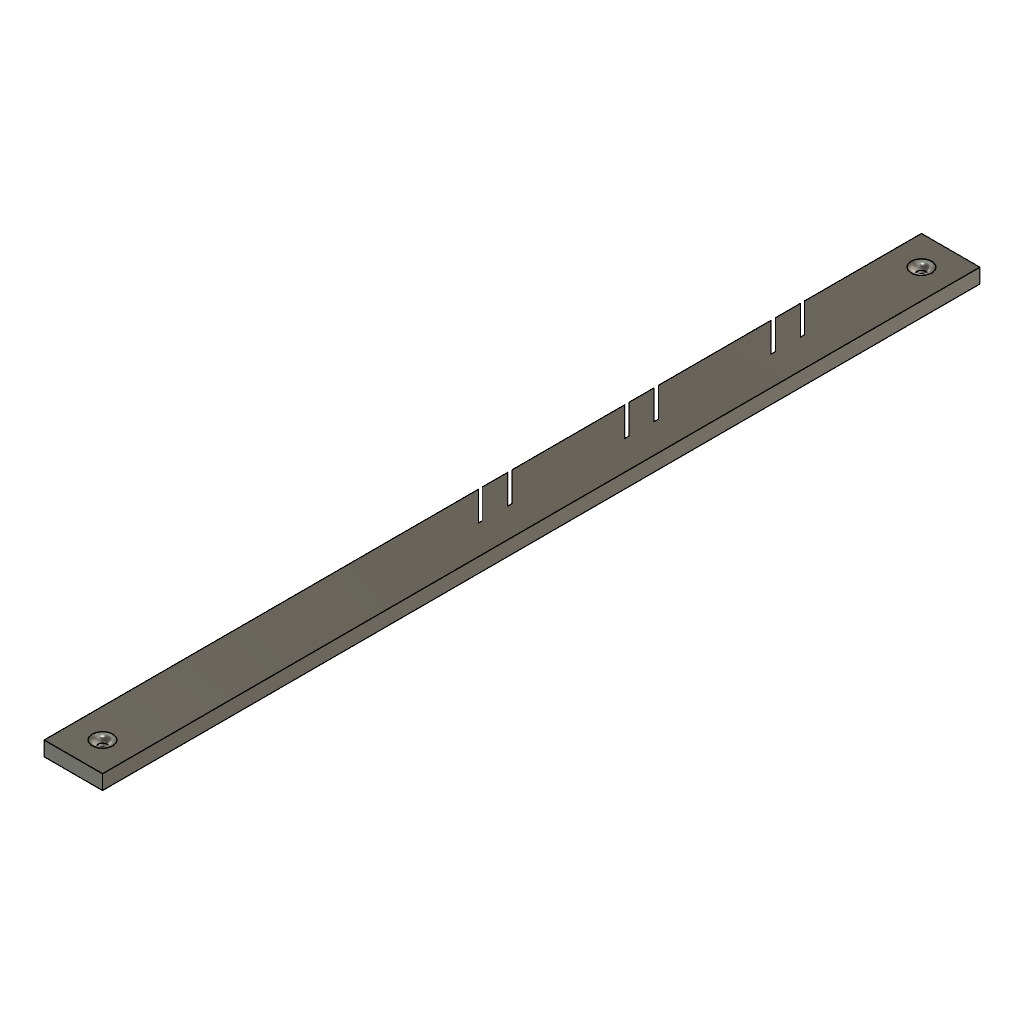
Pilar_x4 (Autodesk Fusion 360 design; units mm, degrees)
part number: 2026-09-25-07-34-19-894
Autodesk Fusion 360 part; units mm, degrees
sketch "Boceto1" plane through (0, 0, 0) normal (0, 0, 1) x (1, 0, 0)
  line L0 (0, 0) -> (20, 0)
  line L1 (20, 0) -> (20, 300)
  line L2 (20, 300) -> (0, 300)
  line L3 (0, 300) -> (0, 0)
  circle A0 centre (10, 10) radius 1.5
  line L4 (20, 150) -> (0, 150)
  line L5 (10, 150) -> (0, 160)
  line L6 (10, 140) -> (0, 150)
  line L7 (10, 190) -> (0, 200)
  line L8 (10, 200) -> (0, 210)
  line L9 (10, 150) -> (10, 200)
  line L10 (10, 200) -> (10, 250)
  line L11 (10, 250) -> (0, 260)
  line L12 (10, 240) -> (0, 250)
  circle A1 centre (10, 290) radius 1.5
  line L13 (0, 258.5858) -> (10, 248.5858)
  line L14 (10, 238.5858) -> (0, 248.5858)
  line L15 (0, 208.5858) -> (10, 198.5858)
  line L16 (0, 198.5858) -> (10, 188.5858)
  line L17 (0, 158.5858) -> (9.7929, 148.7929)
  line L18 (0, 148.5858) -> (9.7929, 138.7929)
  line L19 (10, 150) -> (10, 138.5858)
  line L20 (10, 138.5858) -> (9.7929, 138.7929)
  line L21 (9.7929, 148.7929) -> (10, 148.5858)
  dimension "d1" = 300
  dimension "d2" = 20
  dimension "d3" = 3
  dimension "d4" = 10
  dimension "d5" = 10
  dimension "d6" = 50
  dimension "d7" = 3
  dimension "d8" = 10
  dimension "d9" = 1
  dimension "d10" = 1
  dimension "d11" = 1
  dimension "d12" = 1
  dimension "d13" = 1
  dimension "d14" = 1
  constraint horizontal L0
  constraint vertical L1
  constraint horizontal L2
  constraint vertical L3
  constraint coincident L0.start L3.end
  constraint midpoint L1 L4.start
  constraint midpoint L3 L4.end
  constraint midpoint L4 L5.start
  constraint coincident L3 L7.end
  constraint coincident L3 L5.end
  constraint coincident L3 L8.end
  constraint perpendicular L4 L9
  constraint parallel L9 L10
  constraint coincident L3 L11.end
  constraint coincident L10 L12.start
  constraint coincident L3 L12.end
  constraint coincident L3 L13.start
  constraint coincident L10 L13.end
  constraint parallel L11 L13
  constraint coincident L10 L14.start
  constraint coincident L3 L14.end
  constraint parallel L12 L14
  constraint coincident L3 L15.start
  constraint coincident L9 L15.end
  constraint coincident L3 L16.start
  constraint coincident L9 L16.end
  constraint parallel L7 L16
  constraint coincident L3 L17.start
  constraint parallel L5 L17
  constraint coincident L3 L18.start
  constraint parallel L6 L18
  constraint perpendicular L4 L19
  constraint parallel L18 L20
  constraint coincident L19 L21.end
  constraint parallel L17 L21
  measures "d1" distance of L0.end L1.end
  measures "d2" distance of L0.start L0.end
  measures "d3" diameter of A0
  measures "d4" distance of L3 A0.centre
  measures "d5" distance of L0 A0.centre
  measures "d6" distance of L5.start L8.start
  measures "d7" diameter of A1
  measures "d8" distance of L2 A1.centre
  measures "d9" distance of L11 L13
  measures "d10" distance of L12 L14
  measures "d11" distance of L8 L15
  measures "d12" distance of L7 L16
  measures "d13" distance of L5 L17
  measures "d14" distance of L6 L18
extrude "Extruir1" add sketch "Boceto1" along normal blind 5 contours L0 L1 L3 L4 L18 L19 L20 | L1 L2 L3 L4 L9 L10 L11 | L3 L4 L17 | L4 L6 L17 L19 L21 | L3 L5 L9 L16 | L3 L7 L9 L15 | L3 L10 L12 L13 | L3 L8 L10 L14
fillet "Empalme1" radius 2 4 edges at (8.6015, 290.5424, 5) (8.6015, 10.5424, 5) (8.6015, 290.5424, 0) (8.6015, 10.5424, 0)
